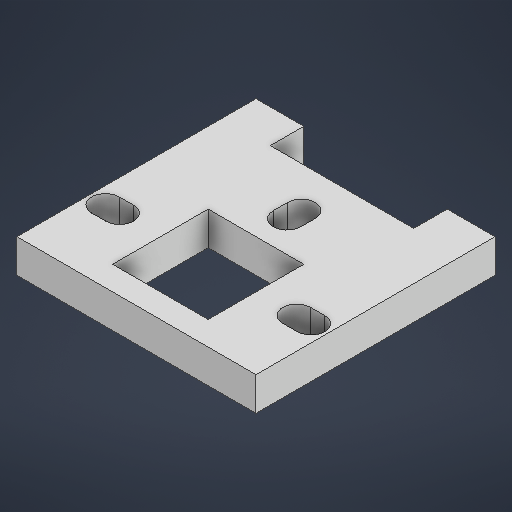
# Autodesk Inventor part: test1
Saved by Autodesk Inventor 2027.1 (Build 311270010, 270A)
## iProperties
Created: 2026-11-15
Part Number: test1
Material: Generic
Document SubType Name: Modeling
Designer: SDS Scholar
Density: 1 g/cm^3
Appearance: Default
Author: SDS Scholar
Autodesk Inventor part; units mm, degrees
ref_plane "YZ Plane" through (0, 0, 0) normal (1, 0, 0) x (0, 1, 0)
ref_plane "XZ Plane" through (0, 0, 0) normal (0, 1, 0) x (-1, 0, 0)
ref_plane "XY Plane" through (0, 0, 0) normal (0, 0, 1) x (1, 0, 0)
sketch "Sketch1" plane through (0, 0, 0) normal (0, 1, 0) x (-1, 0, 0)
  line L0 (-25, 25) -> (25, 25)
  line L1 (25, 25) -> (25, -25)
  line L2 (25, -25) -> (-25, -25)
  line L3 (-25, -25) -> (-25, 25)
  line L4 (-25, 25) -> (25, -25) construction
  line L5 (25, 25) -> (-25, -25) construction
  line L6 (25, -25) -> (-25, -25)
  line L7 (-25, -25) -> (-25, -18)
  line L8 (-25, -18) -> (25, -18)
  line L9 (25, -18) -> (25, -25)
  line L10 (15, -18) -> (-15, -18)
  line L11 (-15, -18) -> (-15, -25)
  line L12 (-15, -25) -> (15, -25)
  line L13 (15, -25) -> (15, -18)
  line L14 (-10, 20) -> (10, 20)
  line L15 (10, 20) -> (10, 0)
  line L16 (10, 0) -> (-10, 0)
  line L17 (-10, 0) -> (-10, 20)
  line L18 (-10, 20) -> (10, 0) construction
  line L19 (10, 20) -> (-10, 0) construction
  line L20 (18.5, 10) -> (21.5, 10) construction
  line L21 (18.5, 7.1) -> (21.5, 7.1)
  line L22 (21.5, 12.9) -> (18.5, 12.9)
  arc A0 (18.5, 12.9) -> (18.5, 7.1) centre (18.5, 10) ccw
  arc A1 (21.5, 7.1) -> (21.5, 12.9) centre (21.5, 10) ccw
  line L23 (0, -9.5) -> (0, -6.5) construction
  line L24 (2.9, -9.5) -> (2.9, -6.5)
  line L25 (-2.9, -6.5) -> (-2.9, -9.5)
  arc A2 (-2.9, -9.5) -> (2.9, -9.5) centre (0, -9.5) ccw
  arc A3 (2.9, -6.5) -> (-2.9, -6.5) centre (0, -6.5) ccw
  line L26 (0, 0) -> (0, 20) construction
  line L27 (-18.5, 10) -> (-21.5, 10) construction
  line L28 (-18.5, 7.1) -> (-21.5, 7.1)
  line L29 (-21.5, 12.9) -> (-18.5, 12.9)
  arc A4 (-18.5, 7.1) -> (-18.5, 12.9) centre (-18.5, 10) ccw
  arc A5 (-21.5, 12.9) -> (-21.5, 7.1) centre (-21.5, 10) ccw
  point P0 (0, -18)
  point P1 (0, -18)
  point P2 (0, 10)
  point P3 (0, 25)
  point P4 (20, 10)
  point P5 (0, -8)
  point P6 (0, -25)
  point P7 (-20, 10)
  dimension "d0" = 50
  dimension "d1" = 50
  dimension "d4" = 7
  dimension "d5" = 30
  dimension "d6" = 20
  dimension "d7" = 20
  dimension "d8" = 5
  dimension "d9" = 3
  dimension "d10" = 5.8
  dimension "d11" = 8.5
  dimension "d12" = 3
  dimension "d13" = 5.8
  dimension "d14" = 8.5
  constraints: 66 end point, 12 point on circle, 10 midpoint, 10 parallel, 8 tangent, 7 symmetric about line, 6 centre point, 5 horizontal, 5 perpendicular, 3 point on line, 2 vertical alignment, 1 coincident, 1 horizontal alignment, 2 other
  measures "d0" distance of L1.end L2.end
  measures "d1" distance of L0.end L1.end
  measures "d4" distance between parallel lines of L2 L8
  measures "d5" distance of L12.end L11.end
  measures "d6" distance of L15.end L16.end
  measures "d7" distance of L14.end L15.end
  measures "d8" distance between parallel lines of L0 L14
  measures "d9" distance of L20.start L20.end
  measures "d10" diameter of A1
  measures "d11" distance from line of L15 L20.start
  measures "d12" distance of L23.start L23.end
  measures "d13" diameter of A3
  measures "d14" distance from line of L10 L23.start
extrude "Extrusion1" add sketch "Sketch1" along normal blind 7 contours L0 L1 L8 L3 | L8 L11 L2 L3 | L1 L2 L13 L8
body "Solid1"
